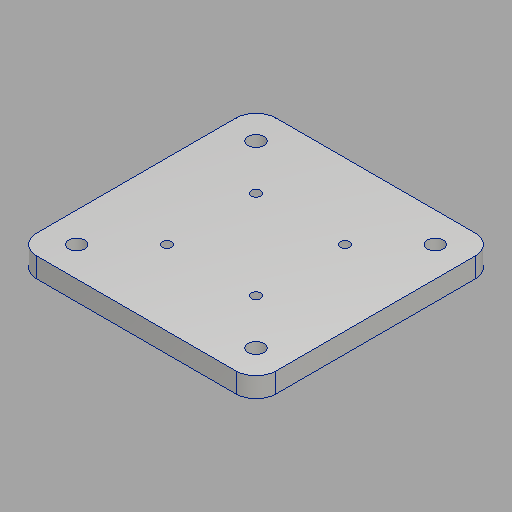
# Autodesk Inventor part: BT006_bensen22_26
Saved by Autodesk Inventor 2025.3 (Build 293356000, 356)
## iProperties
Company: HTBLA Kaindorf
RuleStatus: InUse
Created: 2026-08-10
Part Number: BT006_bensen22_26
Project: Biegeroboter
Material: Aluminium 6061
Description: gehäuse_motor_deckel_v2
Document SubType Name: Modeling
Designer: bensen22
Density: 2.7 g/cm^3
Appearance: Aluminium - flach
Mass: 378.107 g
Surface Area: 342.653 cm^2
Volume: 140.04 cm^3
AfterDocNew0: iProperties-Editor_aufrufen
Author: sebas
Keywords: 2026
Autodesk Inventor part; units mm, degrees
ref_plane "YZ Plane" through (0, 0, 0) normal (1, 0, 0) x (0, 1, 0)
ref_plane "XZ Plane" through (0, 0, 0) normal (0, 1, 0) x (-1, 0, 0)
ref_plane "XY Plane" through (0, 0, 0) normal (0, 0, 1) x (1, 0, 0)
sketch "Skizze3" plane through (0, 0, 0) normal (0, 0, 1) x (1, 0, 0)
  line L0 (-50, 60) -> (50, 60)
  line L1 (60, 50) -> (60, -50)
  line L2 (50, -60) -> (-50, -60)
  line L3 (-60, -50) -> (-60, 50)
  line L4 (-86.8995, 0) -> (86.8995, 0) projected
  line L5 (0, -86.8995) -> (0, 86.8995) projected
  arc A0 (-50, 60) -> (-60, 50) centre (-50, 50) ccw
  arc A1 (60, 50) -> (50, 60) centre (50, 50) ccw
  arc A2 (-60, -50) -> (-50, -60) centre (-50, -50) ccw
  arc A3 (50, -60) -> (60, -50) centre (50, -50) ccw
  point P0 (0, 0)
  point P1 (-60, 60)
  point P2 (60, 60)
  point P3 (-45, 45)
  point P4 (45, 45)
  point P5 (-45, -45)
  point P6 (45, -45)
  dimension "d4" = 120
  dimension "d5" = 120
  dimension "d6" = 10
  dimension "d7" = 10
  dimension "d8" = 15
  dimension "d9" = 15
  constraints: 8 end point, 8 point on circle, 8 tangent, 4 centre point, 4 point on line, 3 symmetric about line, 2 equal radius, 2 parallel, 1 horizontal, 1 perpendicular, 2 other
  measures "d4" distance between parallel lines of L2 L0
  measures "d5" distance of point (-60, 60) point (60, 60)
  measures "d6" radius of A0
  measures "d7" radius of A1
  measures "d8" distance from line of L0 point (-45, 45)
  measures "d9" distance from line of L3 point (-45, 45)
extrude "Extrusion3" add sketch "Skizze3" along normal blind 10
hole "Bohrung1" at (-45, 45, 0) at (45, 45, 0) at (-45, -45, 0) at (45, -45, 0) direction (0, 0, 1) diameter 8 depth 10
sketch "Skizze5" plane through (0, 0, 10) normal (0, 0, 1) x (1, 0, 0)
  line L0 (-84, 0) -> (84, 0) projected
  line L1 (0, -84) -> (0, 84) projected
  circle A0 centre (22.274, -22.274) radius 3
  circle A1 centre (22.274, 22.274) radius 3
  circle A2 centre (-22.274, 22.274) radius 3
  circle A3 centre (-22.274, -22.274) radius 3
  point P0 (0, 0)
  dimension "d72" = 44.548
  dimension "d73" = 44.548
  dimension "d74" = 44.548
  dimension "d75" = 44.548
  dimension "d76" = 6
  dimension "d77" = 6
  dimension "d78" = 6
  dimension "d79" = 6
  constraints: 4 centre point, 4 coincident, 2 symmetric about line
  measures "d72" distance of point (-22.274, -22.274) point (22.274, -22.274)
  measures "d73" distance of point (22.274, -22.274) point (22.274, 22.274)
  measures "d74" distance of point (-22.274, 22.274) point (22.274, 22.274)
  measures "d75" distance of point (-22.274, -22.274) point (-22.274, 22.274)
  measures "d76" diameter of A0
  measures "d77" diameter of A1
  measures "d78" diameter of A2
  measures "d79" diameter of A3
hole "Bohrung2" at (-22.274, 22.274, 10) at (-22.274, -22.274, 10) at (22.274, -22.274, 10) at (22.274, 22.274, 10) direction (0, 0, -1) diameter 4.917 end through all thread size "M6x1" class "6H" standard "ISO Metric profile"
sketch "Skizze7" plane through (0, 0, 10) normal (0, 0, 1) x (1, 0, 0)
  line L0 (-84, 0) -> (84, 0) projected
  line L1 (0, -84) -> (0, 84) projected
  circle A0 centre (0, 0) radius 45
  circle A1 centre (0, 0) radius 46
  point P0 (46, 0)
  point P1 (45, 0)
  point P2 (-45, 0)
  point P3 (-46, 0)
  point P4 (0, 46)
  point P5 (0, -46)
  point P6 (0, -45)
  point P7 (0, 45)
  dimension "d96" = 90
  dimension "d97" = 92
  constraints: 2 centre point, 2 coincident
  measures "d96" diameter of A0
  measures "d97" diameter of A1
extrude "Extrusion5" [suppressed]
sketch "Skizze8" plane through (0, 0, 0) normal (0, 0, -1) x (-1, 0, 0)
  line L0 (84, 0) -> (-84, 0) projected
  line L1 (0, -84) -> (0, 84) projected
  point P0 (0, 0)
  point P1 (22.274, 22.274)
  point P2 (22.274, -22.274)
  point P3 (-22.274, 22.274)
  point P4 (-22.274, -22.274)
  dimension "d100" = 44.548
  dimension "d101" = 44.548
  dimension "d102" = 44.548
  dimension "d103" = 44.548
  measures "d100" distance of point (-22.274, 22.274) point (22.274, 22.274)
  measures "d101" distance of point (-22.274, -22.274) point (-22.274, 22.274)
  measures "d102" distance of point (22.274, -22.274) point (-22.274, -22.274)
  measures "d103" distance of point (22.274, 22.274) point (22.274, -22.274)
hole "Bohrung4" at (-22.274, 22.274, 0) at (-22.274, -22.274, 0) at (22.274, 22.274, 0) at (22.274, -22.274, 0) direction (0, 0, 1) diameter 4.917 end through all countersink diameter 10.5 countersink angle 90 thread size "M6x1" class "6H" standard "ISO Metric profile"
